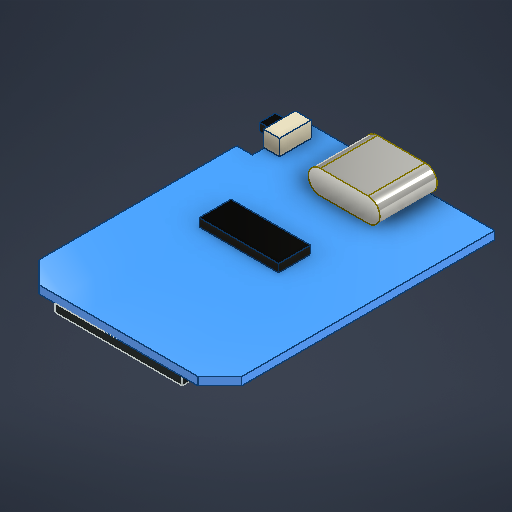
# Autodesk Inventor part: ESP32-D1mini
Saved by Autodesk Inventor 2027.1 (Build 311270010, 270A)
## iProperties
Created: 2026-09-25
Part Number: ESP32-D1mini
Material: 페놀 수지
Document SubType Name: Modeling
Designer: work
Density: 1.38 g/cm^3
Appearance: 시안색
Author: work
Autodesk Inventor part; units mm, degrees
ref_plane "YZ Plane" through (0, 0, 0) normal (1, 0, 0) x (0, 1, 0)
ref_plane "XZ Plane" through (0, 0, 0) normal (0, 1, 0) x (-1, 0, 0)
ref_plane "XY Plane" through (0, 0, 0) normal (0, 0, 1) x (1, 0, 0)
sketch "스케치1" plane through (0, 0, 0) normal (0, 1, 0) x (-1, 0, 0)
  line L0 (0, 0) -> (25.5, 0)
  line L1 (25.5, 0) -> (25.5, -34.6)
  line L2 (25.5, -34.6) -> (0, -34.6)
  line L3 (0, -34.6) -> (0, 0)
  line L4 (25.5, -27.6) -> (23.5, -27.6)
  line L5 (23.5, -27.6) -> (23.5, -34.6)
  line L6 (23.5, -34.6) -> (25.5, -34.6)
  line L7 (25.5, -34.6) -> (25.5, -27.6)
  line L8 (12.75, -34.6) -> (12.75, 0) construction
  line L9 (22.75, 0) -> (25.5, -2.75)
  line L10 (2.75, 0) -> (0, -2.75)
  dimension "d0" = 25.5
  dimension "d1" = 34.6
  dimension "d2" = 2
  dimension "d3" = 7
  dimension "d4" = 45
  dimension "d5" = 20
  constraints: 22 end point, 4 parallel, 4 point on line, 2 horizontal, 2 midpoint, 2 perpendicular, 2 symmetric about line
  measures "d0" distance of L1.end L2.end
  measures "d1" distance of L0.end L1.end
  measures "d2" distance of L4.start L4.end
  measures "d3" distance of L4.end L5.end
  measures "d4" angle of L0 L9
  measures "d5" distance of L10.start L9.start
extrude "돌출1" add sketch "스케치1" along normal blind 1 contours L0 L9 L1 L4 L5 L2 L3 L10
sketch "스케치2" plane through (0, 0, 0) normal (0, -1, 0) x (1, 0, 0)
  line L0 (-4.75, 0) -> (-20.75, 0)
  line L1 (-20.75, 0) -> (-20.75, -24)
  line L2 (-20.75, -24) -> (-4.75, -24)
  line L3 (-4.75, -24) -> (-4.75, 0)
  line L4 (-22.75, 0) -> (-2.75, 0) projected
  point P0 (0, 0)
  point P1 (-12.75, 0)
  dimension "d8" = 24
  dimension "d9" = 16
  constraints: 8 end point, 2 midpoint, 2 parallel, 1 horizontal, 1 perpendicular
  measures "d8" distance of L0.end L1.end
  measures "d9" distance of L1.end L2.end
extrude "돌출2" add sketch "스케치2" along normal blind 1 separate body
sketch "스케치3" plane through (0, -1, 0) normal (0, -1, 0) x (1, 0, 0)
  line L0 (-6.5, -8) -> (-19, -8)
  line L1 (-19, -8) -> (-19, -23)
  line L2 (-19, -23) -> (-6.5, -23)
  line L3 (-6.5, -23) -> (-6.5, -8)
  line L4 (-20.75, -24) -> (-4.75, -24) projected
  point P0 (0, 0)
  point P1 (-12.75, -24)
  point P2 (-12.75, -23)
  dimension "d12" = 12.5
  dimension "d13" = 15
  dimension "d14" = 1
  constraints: 8 end point, 2 midpoint, 2 parallel, 1 horizontal, 1 perpendicular, 1 vertical alignment
  measures "d12" distance of L2.end L1.end
  measures "d13" distance of L1.end L0.end
  measures "d14" distance between parallel lines of L4 L2
extrude "돌출3" add sketch "스케치3" along normal blind 2 separate body
sketch "스케치4" plane through (0, 1, 0) normal (0, 1, 0) x (1, 0, 0)
  line L0 (-23.5, 29.1) -> (-21.6, 29.1)
  line L1 (-21.6, 29.1) -> (-21.6, 33.1)
  line L2 (-21.6, 33.1) -> (-23.5, 33.1)
  line L3 (-23.5, 33.1) -> (-23.5, 29.1)
  line L4 (-23.5, 34.6) -> (-23.5, 27.6) projected
  line L5 (-23.5, 29.1) -> (-23.6, 29.1)
  line L6 (-23.6, 29.1) -> (-23.6, 33.1)
  line L7 (-23.6, 33.1) -> (-23.5, 33.1)
  line L8 (-23.5, 33.1) -> (-23.5, 29.1)
  point P0 (0, 0)
  point P1 (-23.5, 31.1)
  dimension "d17" = 4
  dimension "d21" = 2
  dimension "d22" = 0.1
  constraints: 16 end point, 4 parallel, 2 horizontal, 2 midpoint, 2 perpendicular
  measures "d17" distance of L0.end L1.end
  measures "d21" distance between parallel lines of L1 L6
  measures "d22" distance between parallel lines of L3 L6
extrude "돌출4" add sketch "스케치4" along normal blind 2 bodies 1
sketch "스케치5" plane through (0, 0, -34.6) normal (0, 0, -1) x (-1, 0, 0)
  line L0 (14.75, 2.5) -> (8.75, 2.5) construction
  line L1 (14.75, 4) -> (8.75, 4)
  line L2 (8.75, 1) -> (14.75, 1)
  arc A0 (14.75, 1) -> (14.75, 4) centre (14.75, 2.5) ccw
  arc A1 (8.75, 4) -> (8.75, 1) centre (8.75, 2.5) ccw
  line L3 (0, 1) -> (23.5, 1) projected
  line L4 (14.75, 3.8) -> (8.75, 3.8)
  arc A2 (8.75, 3.8) -> (8.75, 1.2) centre (8.75, 2.5) ccw
  line L5 (8.75, 1.2) -> (14.75, 1.2)
  arc A3 (14.75, 1.2) -> (14.75, 3.8) centre (14.75, 2.5) ccw
  point P0 (0, 0)
  point P1 (11.75, 2.5)
  point P2 (16.25, 2.5)
  point P3 (7.25, 2.5)
  point P4 (11.75, 1)
  dimension "d23" = 3
  dimension "d24" = 9
  dimension "d25" = 0.2
  constraints: 12 end point, 10 point on circle, 4 centre point, 4 tangent, 3 midpoint, 2 parallel, 1 horizontal, 3 other
  measures "d23" distance between parallel lines of L2 L1
  measures "d24" distance of point (16.25, 2.5) point (7.25, 2.5)
  measures "d25" radial gap between concentric circles of A0 A3
extrude "돌출5" add sketch "스케치5" against normal blind 7.2 separate body
sketch "스케치6" plane through (0, 0, -27.4) normal (0, 0, 1) x (1, 0, 0)
  arc A0 (-14.75, 4) -> (-14.75, 1) centre (-14.75, 2.5) ccw projected
  arc A1 (-8.75, 1) -> (-8.75, 4) centre (-8.75, 2.5) ccw projected
  line L0 (-8.75, 4) -> (-14.75, 4) projected
  arc A2 (-14.75, 4) -> (-14.75, 1) centre (-14.75, 2.5) ccw projected
  line L1 (-14.75, 1) -> (-8.75, 1) projected
  arc A3 (-14.75, 3.8) -> (-14.75, 1.2) centre (-14.75, 2.5) ccw projected
  line L2 (-14.75, 3.8) -> (-8.75, 3.8) projected
  arc A4 (-8.75, 1.2) -> (-8.75, 3.8) centre (-8.75, 2.5) ccw projected
  line L3 (-8.75, 1.2) -> (-14.75, 1.2) projected
  point P0 (0, 0)
  point P1 (-14.75, 4)
  point P2 (-14.75, 1)
extrude "돌출6" add sketch "스케치6" against normal blind 0.2 contours L0 A1 L1 A0 | L2 A4 L3 A3 bodies 4
sketch "스케치7" plane through (0, 1, 0) normal (0, 1, 0) x (1, 0, 0)
  line L0 (-19, 23) -> (-19, 8) projected
  line L1 (-19, 16.4) -> (-9, 16.4)
  line L2 (-9, 16.4) -> (-9, 20.4)
  line L3 (-9, 20.4) -> (-19, 20.4)
  line L4 (-19, 20.4) -> (-19, 16.4)
  line L5 (-8.75, 27.4) -> (-14.75, 27.4) projected
  point P0 (0, 0)
  dimension "d30" = 10
  dimension "d31" = 4
  dimension "d32" = 7
  constraints: 8 end point, 2 parallel, 1 horizontal, 1 perpendicular, 1 point on line
  measures "d30" distance of L2.end L3.end
  measures "d31" distance of L1.end L2.end
  measures "d32" distance between parallel lines of L5 L3
extrude "돌출7" add sketch "스케치7" along normal blind 1 bodies 1
fillet "모깎기1" radius 0.2 8 edges at (-19, -2, -23) (-12.75, -3, -23) (-19, -3, -15.5) (-6.5, -2, -23) (-6.5, -3, -15.5) (-12.75, -3, -8) (-6.5, -2, -8) (-19, -2, -8)
sketch "스케치8" plane through (-23.6, 1, -33.1) normal (-1, 0, 0) x (0, 0, 1)
  line L0 (1, 1.5) -> (3, 1.5)
  line L1 (3, 1.5) -> (3, 0.5)
  line L2 (3, 0.5) -> (1, 0.5)
  line L3 (1, 0.5) -> (1, 1.5)
  line L4 (0, 0) -> (4, 0) projected
  line L5 (4, 0) -> (4, 2) projected
  point P0 (33.1, -1)
  point P1 (2, 0.5)
  point P2 (2, 0)
  point P3 (3, 1)
  point P4 (4, 1)
  dimension "d36" = 2
  dimension "d37" = 1
  constraints: 8 end point, 4 midpoint, 2 parallel, 1 horizontal, 1 horizontal alignment, 1 perpendicular, 1 vertical alignment
  measures "d36" distance of L1.end L2.end
  measures "d37" distance of L0.end L1.end
extrude "돌출8" add sketch "스케치8" along normal blind 1.5 separate body
sketch "스케치9" plane through (0, -1, 0) normal (0, -1, 0) x (1, 0, 0)
  line L0 (-20.25, -7) -> (-19.75, -7)
  line L1 (-19.75, -7) -> (-19.75, -1)
  line L2 (-19.75, -1) -> (-20.25, -1)
  line L3 (-20.25, -1) -> (-20.25, -7)
  line L4 (-20.25, -1) -> (-14.75, -1)
  line L5 (-14.75, -1) -> (-14.75, -0.5)
  line L6 (-14.75, -0.5) -> (-20.25, -0.5)
  line L7 (-20.25, -0.5) -> (-20.25, -1)
  line L8 (-15.25, -1) -> (-14.75, -1)
  line L9 (-14.75, -1) -> (-14.75, -4)
  line L10 (-14.75, -4) -> (-15.25, -4)
  line L11 (-15.25, -4) -> (-15.25, -1)
  line L12 (-14.75, -4) -> (-12.75, -4)
  line L13 (-12.75, -4) -> (-12.75, -3.5)
  line L14 (-12.75, -3.5) -> (-14.75, -3.5)
  line L15 (-14.75, -3.5) -> (-14.75, -4)
  line L16 (-12.75, -4) -> (-12.25, -4)
  line L17 (-12.25, -4) -> (-12.25, -0.5)
  line L18 (-12.25, -0.5) -> (-12.75, -0.5)
  line L19 (-12.75, -0.5) -> (-12.75, -4)
  line L20 (-12.25, -0.5) -> (-9.75, -0.5)
  line L21 (-9.75, -0.5) -> (-9.75, -1)
  line L22 (-9.75, -1) -> (-12.25, -1)
  line L23 (-12.25, -1) -> (-12.25, -0.5)
  line L24 (-10.25, -1) -> (-9.75, -1)
  line L25 (-9.75, -1) -> (-9.75, -4)
  line L26 (-9.75, -4) -> (-10.25, -4)
  line L27 (-10.25, -4) -> (-10.25, -1)
  line L28 (-9.75, -4) -> (-7.75, -4)
  line L29 (-7.75, -4) -> (-7.75, -3.5)
  line L30 (-7.75, -3.5) -> (-9.75, -3.5)
  line L31 (-9.75, -3.5) -> (-9.75, -4)
  line L32 (-7.75, -4) -> (-7.25, -4)
  line L33 (-7.25, -4) -> (-7.25, -0.5)
  line L34 (-7.25, -0.5) -> (-7.75, -0.5)
  line L35 (-7.75, -0.5) -> (-7.75, -4)
  line L36 (-7.25, -0.5) -> (-5.25, -0.5)
  line L37 (-5.25, -0.5) -> (-5.25, -1)
  line L38 (-5.25, -1) -> (-7.25, -1)
  line L39 (-7.25, -1) -> (-7.25, -0.5)
  line L40 (-5.75, -1) -> (-5.25, -1)
  line L41 (-5.25, -1) -> (-5.25, -7)
  line L42 (-5.25, -7) -> (-5.75, -7)
  line L43 (-5.75, -7) -> (-5.75, -1)
  line L44 (-17.75, -1) -> (-17.25, -1)
  line L45 (-17.25, -1) -> (-17.25, -7)
  line L46 (-17.25, -7) -> (-17.75, -7)
  line L47 (-17.75, -7) -> (-17.75, -1)
  line L48 (-20.75, 0) -> (-20.75, -24) projected
  line L49 (-4.75, -24) -> (-4.75, 0) projected
  line L50 (-4.75, 0) -> (-20.75, 0) projected
  line L51 (-6.7, -8) -> (-18.8, -8) projected
  point P0 (0, 0)
  point P1 (-17.5, -7)
  point P2 (-20, -7)
  point P3 (-5.5, -7)
  point P4 (-17.75, -4)
  point P5 (-15.25, -2.5)
  point P6 (-12.75, -2.25)
  point P7 (-10.25, -2.5)
  point P8 (-17.25, -4)
  point P9 (-19.75, -1)
  dimension "d40" = 0.5
  dimension "d41" = 0.5
  dimension "d42" = 0.5
  dimension "d43" = 0.5
  dimension "d44" = 0.5
  dimension "d45" = 0.5
  dimension "d46" = 0.5
  dimension "d47" = 0.5
  dimension "d48" = 0.5
  dimension "d49" = 0.5
  dimension "d50" = 0.5
  dimension "d51" = 0.5
  dimension "d52" = 1
  dimension "d53" = 1
  dimension "d54" = 1
  dimension "d55" = 2
  dimension "d58" = 2
  dimension "d59" = 2
  dimension "d60" = 2
  dimension "d61" = 2
  dimension "d62" = 0.5
  constraints: 96 end point, 24 parallel, 12 horizontal, 12 perpendicular, 12 point on line, 8 midpoint, 1 horizontal alignment
  measures "d40" distance between parallel lines of L1 L3
  measures "d41" distance between parallel lines of L4 L6
  measures "d42" distance between parallel lines of L45 L47
  measures "d43" distance between parallel lines of L9 L11
  measures "d44" distance between parallel lines of L12 L14
  measures "d45" distance between parallel lines of L17 L19
  measures "d46" distance between parallel lines of L25 L27
  measures "d47" distance between parallel lines of L33 L35
  measures "d48" distance between parallel lines of L41 L43
  measures "d49" distance between parallel lines of L48 L3
  measures "d50" distance between parallel lines of L49 L41
  measures "d51" distance between parallel lines of L50 L6
  measures "d52" distance from line of L51 point (-17.5, -7)
  measures "d53" distance from line of L51 point (-20, -7)
  measures "d54" distance from line of L51 point (-5.5, -7)
  measures "d55" distance from line of point (-17.75, -4) L1
  measures "d58" distance from line of point (-15.25, -2.5) L45
  measures "d59" distance from line of point (-12.75, -2.25) L9
  measures "d60" distance from line of point (-10.25, -2.5) L17
  measures "d61" distance between parallel lines of L25 L35
  measures "d62" distance between parallel lines of L36 L38
extrude "돌출9" cut sketch "스케치9" against normal blind 0.1 bodies 2
equation "\"d58\" = d55"
equation "\"d59\" = d58"
equation "\"d60\" = d59"
equation "\"d61\" = d55"
